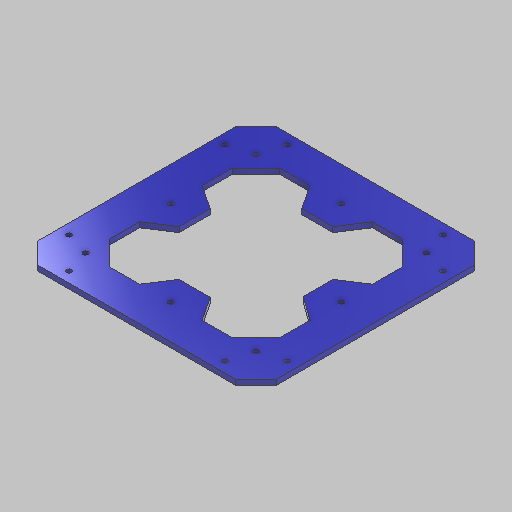
# Autodesk Inventor part: Armadura_Base_interna
Saved by Autodesk Inventor 2027 (Build 310192000, 192)
## iProperties
Created: 2026-11-23
Part Number: Armadura_Base_interna
Material: Genérico
Document SubType Name: Modeling
Designer: Alexander
Density: 1 g/cm^3
Appearance: Valor por defecto
Author: Alexander
Autodesk Inventor part; units mm, degrees
ref_plane "YZ Plane" through (0, 0, 0) normal (1, 0, 0) x (0, 1, 0)
ref_plane "XZ Plane" through (0, 0, 0) normal (0, 1, 0) x (-1, 0, 0)
ref_plane "XY Plane" through (0, 0, 0) normal (0, 0, 1) x (1, 0, 0)
sketch "Boceto1" plane through (0, 0, 0) normal (0, 1, 0) x (-1, 0, 0)
  line L0 (115, 115) -> (-115, 115)
  line L1 (-115, 115) -> (-115, -115)
  line L2 (-115, -115) -> (115, -115)
  line L3 (115, -115) -> (115, 115)
  line L4 (59, 59) -> (-59, 59)
  line L5 (-59, 59) -> (-59, -59)
  line L6 (-59, -59) -> (59, -59)
  line L7 (59, -59) -> (59, 59)
  circle A0 centre (0, 82) radius 2.5
  circle A1 centre (0, -82) radius 2.5
  circle A2 centre (82, 0) radius 2.5
  circle A3 centre (-82, 0) radius 2.5
  line L8 (0, 82) -> (82, 82)
  line L9 (82, 82) -> (82, 0)
  line L10 (82, 0) -> (0, 0)
  line L11 (0, 0) -> (0, 82)
  line L12 (-82, 0) -> (0, 0)
  line L13 (0, 0) -> (0, -82)
  line L14 (0, -82) -> (-82, -82)
  line L15 (-82, -82) -> (-82, 0)
  line L16 (0, -82) -> (82, -82)
  line L17 (82, -82) -> (82, 0)
  line L18 (82, 0) -> (0, 0)
  line L19 (0, 0) -> (0, -82)
  line L20 (0, 82) -> (-82, 82)
  line L21 (-82, 82) -> (-82, 0)
  line L22 (-82, 0) -> (0, 0)
  line L23 (0, 0) -> (0, 82)
  circle A4 centre (-82, -82) radius 2.5
  circle A5 centre (-82, 82) radius 2.5
  circle A6 centre (82, 82) radius 2.5
  circle A7 centre (82, -82) radius 2.5
  line L24 (30, 115) -> (-30, 115)
  line L25 (-30, 115) -> (-30, 59)
  line L26 (-30, 59) -> (30, 59)
  line L27 (30, 59) -> (30, 115)
  line L28 (115, 30) -> (59, 30)
  line L29 (59, 30) -> (59, -30)
  line L30 (59, -30) -> (115, -30)
  line L31 (115, -30) -> (115, 30)
  line L32 (30, -59) -> (-30, -59)
  line L33 (-30, -59) -> (-30, -115)
  line L34 (-30, -115) -> (30, -115)
  line L35 (30, -115) -> (30, -59)
  line L36 (-115, 32.7706) -> (-115, -28.4069)
  line L37 (-59, -33.4069) -> (-59, 27.7706)
  line L38 (-115, 0) -> (-59, 0)
  line L39 (-59, 0) -> (-59, 30)
  line L40 (-59, 30) -> (-115, 30)
  line L41 (-115, 30) -> (-115, 0)
  line L42 (-115, 0) -> (-59, 0)
  line L43 (-59, 0) -> (-59, -30)
  line L44 (-59, -30) -> (-115, -30)
  line L45 (-115, -30) -> (-115, 0)
  line L46 (115, 115) -> (59, 115)
  line L47 (59, 115) -> (59, 59)
  line L48 (59, 59) -> (115, 59)
  line L49 (115, 59) -> (115, 115)
  line L50 (59, -59) -> (115, -59)
  line L51 (115, -59) -> (115, -115)
  line L52 (115, -115) -> (59, -115)
  line L53 (59, -115) -> (59, -59)
  line L54 (-59, -59) -> (-115, -59)
  line L55 (-115, -59) -> (-115, -115)
  line L56 (-115, -115) -> (-59, -115)
  line L57 (-59, -115) -> (-59, -59)
  line L58 (-59, 59) -> (-115, 59)
  line L59 (-115, 59) -> (-115, 115)
  line L60 (-115, 115) -> (-59, 115)
  line L61 (-59, 115) -> (-59, 59)
  line L62 (-15, 59) -> (-30, 82)
  line L63 (15, 59) -> (30, 82)
  line L64 (59, 15) -> (82, 30)
  line L65 (59, -15) -> (82, -30)
  line L66 (59, 82) -> (82, 59)
  line L67 (82, -59) -> (59, -82)
  line L68 (-59, -82) -> (-82, -59)
  line L69 (-82, 59) -> (-59, 82)
  line L70 (-82, 30) -> (-59, 13.5759)
  line L71 (-59, -15) -> (-82, -30)
  line L72 (-30, -82) -> (-15, -59)
  line L73 (15, -59) -> (30, -82)
  point P0 (0, 0)
  point P1 (-59, 82)
  dimension "d0" = 230
  dimension "d1" = 230
  dimension "d2" = 115
  dimension "d3" = 115
  dimension "d4" = 118
  dimension "d5" = 118
  dimension "d6" = 59
  dimension "d7" = 59
  dimension "d8" = 5
  dimension "d9" = 23
  dimension "d10" = 5
  dimension "d11" = 23
  dimension "d12" = 5
  dimension "d13" = 5
  dimension "d14" = 23
  dimension "d15" = 23
  dimension "d16" = 5
  dimension "d17" = 5
  dimension "d18" = 5
  dimension "d19" = 5
  dimension "d20" = 30
  dimension "d21" = 30
  dimension "d22" = 30
  dimension "d23" = 30
  dimension "d24" = 30
  dimension "d25" = 30
  dimension "d27" = 30
  dimension "d28" = 30
  dimension "d29" = 15
  dimension "d30" = 15
  dimension "d31" = 15
  dimension "d32" = 15
  dimension "d33" = 15
  dimension "d34" = 15
  constraints: 148 end point, 48 point on line, 31 parallel, 17 perpendicular, 15 horizontal, 8 centre point, 4 coincident, 1 midpoint
  measures "d0" distance of L2.end L1.end
  measures "d1" distance of L1.end L0.end
  measures "d2" distance from line of L3 point (0, 0)
  measures "d3" distance from line of L0 point (0, 0)
  measures "d4" distance of L6.end L4.start
  measures "d5" distance of L4.start L4.end
  measures "d6" distance from line of L7 point (0, 0)
  measures "d7" distance from line of point (0, 0) L6
  measures "d8" diameter of A0
  measures "d9" distance from line of L8.start L4
  measures "d10" diameter of A1
  measures "d11" distance from line of L6 L13.end
  measures "d12" diameter of A2
  measures "d13" diameter of A3
  measures "d14" distance from line of L12.start L5
  measures "d15" distance from line of L7 L9.end
  measures "d16" diameter of A4
  measures "d17" diameter of A5
  measures "d18" diameter of A6
  measures "d19" diameter of A7
  measures "d20" distance between parallel lines of L27 L11
  measures "d21" distance between parallel lines of L25 L11
  measures "d22" distance between parallel lines of L28 L10
  measures "d23" distance between parallel lines of L10 L30
  measures "d24" distance between parallel lines of L35 L13
  measures "d25" distance between parallel lines of L33 L19
  measures "d27" distance of L39.end L38.end
  measures "d28" distance of L42.end L43.end
  measures "d29" distance from line of L64.start L28
  measures "d30" distance from line of L65.start L30
  measures "d31" distance from line of L73.start L35
  measures "d32" distance from line of L72.end L33
  measures "d33" distance from line of L63.start L27
  measures "d34" distance from line of L62.start L25
extrude "Extrusión1" add sketch "Boceto1" along normal blind 5 contours L3 L48 L9 A6 L8 L47 L0 | L47 L8 L27 L0 | L3 L28 L9 L48 | L27 L8 A0 L20 L25 L0 | L8 A6 L9 L66 | L3 L30 L17 A2 L9 L28 | L25 L20 L61 L0 | L63 L4 L11 A0 L8 | L3 L50 L17 L30 | L9 A2 L10 L7 L64 | L61 L20 A5 L21 L58 L1 L0 | L20 A0 L11 L4 L62 | L3 L2 L53 L16 A7 L17 L50 | L65 L7 L10 A2 L17 | L69 L21 A5 L20 | L17 A7 L16 L67 | L58 L21 L40 L1 | L2 L35 L16 L53 | L70 L5 L12 A3 L21 | L21 A3 L38 L1 L40 | L5 L71 L15 A3 L12 | L13 A1 L14 L72 L6 | L6 L73 L16 A1 L13 | L2 L33 L14 A1 L16 L35 | L2 L57 L14 L33 | L38 A3 L15 L44 L1 | L15 L54 L1 L44 | L2 L1 L54 L15 A4 L14 L57 | L68 L14 A4 L15
sketch "Boceto2" plane through (0, 5, 0) normal (0, 1, 0) x (1, 0, 0)
  circle A0 centre (-75, -105) radius 2.5
  circle A1 centre (-75, 105) radius 2.5
  circle A2 centre (75, 105) radius 2.5
  circle A3 centre (75, -105) radius 2.5
  point P0 (0, 0)
  dimension "d37" = 5
  dimension "d38" = 5
  dimension "d39" = 210
  dimension "d41" = 5
  dimension "d43" = 150
  dimension "d44" = 5
  dimension "d45" = 210
  dimension "d46" = 105
  dimension "d47" = 75
  dimension "d48" = 75
  constraints: 4 centre point
  measures "d37" diameter of A0
  measures "d38" diameter of A1
  measures "d39" distance of A1.centre A0.centre
  measures "d41" diameter of A2
  measures "d43" distance of A1.centre A2.centre
  measures "d44" diameter of A3
  measures "d45" distance of A2.centre A3.centre
  measures "d46" vertical distance of A0.centre point (0, 0)
  measures "d47" horizontal distance of A1.centre point (0, 0)
  measures "d48" horizontal distance of point (0, 0) A0.centre
extrude "Extrusión2" cut sketch "Boceto2" against normal blind 5
sketch "Boceto3" plane through (0, 5, 0) normal (0, 1, 0) x (1, 0, 0)
  circle A0 centre (-105, -75) radius 2.5
  circle A1 centre (-105, 75) radius 2.5
  circle A2 centre (105, 75) radius 2.5
  circle A3 centre (105, -75) radius 2.5
  point P0 (0, 0)
  dimension "d51" = 105
  dimension "d52" = 105
  dimension "d53" = 105
  dimension "d54" = 105
  dimension "d55" = 75
  dimension "d56" = 75
  dimension "d57" = 75
  dimension "d58" = 75
  dimension "d59" = 5
  dimension "d60" = 5
  dimension "d61" = 5
  dimension "d62" = 5
  constraints: 4 centre point, 4 coincident
  measures "d51" horizontal distance of point (0, 0) point (-105, -75)
  measures "d52" horizontal distance of point (0, 0) point (-105, 75)
  measures "d53" horizontal distance of point (105, -75) point (0, 0)
  measures "d54" horizontal distance of point (105, 75) point (0, 0)
  measures "d55" vertical distance of point (0, 0) point (105, -75)
  measures "d56" vertical distance of point (105, 75) point (0, 0)
  measures "d57" vertical distance of point (-105, -75) point (0, 0)
  measures "d58" vertical distance of point (-105, 75) point (0, 0)
  measures "d59" diameter of A0
  measures "d60" diameter of A1
  measures "d61" diameter of A2
  measures "d62" diameter of A3
extrude "Extrusión3" cut sketch "Boceto3" against normal blind 5
sketch "Boceto4" plane through (0, 5, 0) normal (0, 1, 0) x (1, 0, 0)
  line L0 (-115, -115) -> (115, -115) projected
  line L1 (-115, -115) -> (-95, -115)
  line L2 (-95, -115) -> (-95, -95)
  line L3 (-95, -95) -> (-115, -95)
  line L4 (-115, -95) -> (-115, -115)
  line L5 (-115, 115) -> (-95, 115)
  line L6 (-95, 115) -> (-95, 95)
  line L7 (-95, 95) -> (-115, 95)
  line L8 (-115, 95) -> (-115, 115)
  line L9 (115, -115) -> (115, 115) projected
  line L10 (115, 115) -> (95, 115)
  line L11 (95, 115) -> (95, 95)
  line L12 (95, 95) -> (115, 95)
  line L13 (115, 95) -> (115, 115)
  line L14 (115, -115) -> (95, -115)
  line L15 (95, -115) -> (95, -95)
  line L16 (95, -95) -> (115, -95)
  line L17 (115, -95) -> (115, -115)
  line L18 (-95, -115) -> (-115, -95)
  line L19 (-115, 95) -> (-95, 115)
  line L20 (95, 115) -> (115, 95)
  line L21 (115, -95) -> (95, -115)
  point P0 (0, 0)
  dimension "d65" = 20
  dimension "d66" = 20
  dimension "d67" = 20
  dimension "d68" = 20
  dimension "d69" = 20
  dimension "d70" = 20
  dimension "d71" = 20
  dimension "d72" = 20
  constraints: 40 end point, 8 parallel, 4 horizontal, 4 perpendicular, 1 point on line
  measures "d65" distance of L3.end L2.end
  measures "d66" distance of L2.end L1.end
  measures "d67" distance of L6.end L7.end
  measures "d68" distance of L5.end L6.end
  measures "d69" distance of L12.end L11.end
  measures "d70" distance of L11.end L10.end
  measures "d71" distance of L15.end L16.end
  measures "d72" distance of L14.end L15.end
extrude "Extrusión4" cut sketch "Boceto4" against normal blind 5 contours L4 L18 L0 | L20 L10 L9 | L21 L9 L0 | L5 L19 L8
equation "\"d2\" = 0.5 * d0"
equation "\"d3\" = 0.5 * d1"
equation "\"d6\" = 0.5 * d5"
equation "\"d7\" = 0.5 * d4"
equation "\"d11\" = d9"
equation "\"d14\" = d9"
equation "\"d15\" = d9"
equation "\"d46\" = 0.5 * d39"
equation "\"d47\" = 0.5 * d43"
equation "\"d48\" = 0.5 * d43"
